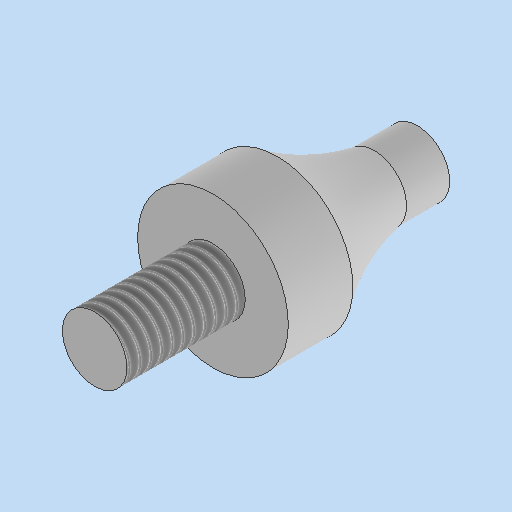
# Autodesk Inventor part: MM0948AN125_G02_100
Saved by Autodesk Inventor 2023.3 (Build 273359000, 359)
## iProperties
Created: 2024-01-18
Part Number: MM0948AN125_G02_100
Material: xStahl_AnP_Dummymaterial
Description: =<RBPARTNOTITLE2>
Vendor: Albert Kuhn
Document SubType Name: Modeling
Designer: RIC7AN
Mass: 1.94193 g
Surface Area: 2.54828 cm^2
Volume: 0.247379 cm^3
Density: 7.85 g/cm^3
Appearance: Vorgabe(1)
RBPARTMADEOF: Hydraulik Schmiernippel H1 M 3 x 0,5, SW7, DIN 71412, Form A, Stahl verzinkt
RBDRAWINGMISSINGSPEC: --
AnP_Kategorie: 2
RBPARTNOTITLE2: Schmiernippel
RBGBREMARKSINDEX: E
RBSURFACE: --
RBPARTNOTITLE1: lubrication nipple
AnP_Material: =<Material>
RBMATERIAL: --
RBMATNO: =<Part Number>
RBPARTNO: SIEHE MNR
Author: RIC7AN
Keywords: =<RBPARTMADEOF>
Comments: =<RBSURFACE2>
Revision Number: 01
Autodesk Inventor part; units mm, degrees
ref_plane "YZ Plane" through (0, 0, 0) normal (1, 0, 0) x (0, 1, 0)
ref_plane "XZ Plane" through (0, 0, 0) normal (0, 1, 0) x (-1, 0, 0)
ref_plane "XY Plane" through (0, 0, 0) normal (0, 0, 1) x (1, 0, 0)
sketch "Skizze1" plane through (0, 0, 0) normal (0, 0, 1) x (1, 0, 0)
  line L0 (0, 0) -> (3.5, 0)
  line L1 (3.5, 0) -> (3.5, 3)
  line L2 (3.5, 3) -> (0, 3)
  line L3 (0, 3) -> (0, 0)
  line L4 (1.3123, 9.5) -> (0, 9.5)
  line L5 (0, 0) -> (1.5, 0)
  line L6 (1.5, 0) -> (1.5, -5.5)
  line L7 (1.5, -5.5) -> (0, -5.5)
  line L8 (0, -5.5) -> (0, 0)
  arc A0 (1.3123, 9.5) -> (3.5, 3) centre (12.0625, 9.5) ccw
  line L9 (0, 9.5) -> (1.5, 9.5)
  line L10 (1.5, 9.5) -> (1.5, 7.5)
  line L11 (1.5, 7.5) -> (0, 7.5)
  line L12 (0, 7.5) -> (0, 9.5)
  line L13 (0, 7.5) -> (0, 3)
  point P0 (0.8535, 7.5)
  dimension "d0" = 1.5
  dimension "d1" = 5.5
  dimension "d2" = 15
  dimension "d3" = 3.5
  dimension "d4" = 1.5
  dimension "d5" = 2
  dimension "d6" = 3
  constraints: 28 end point, 6 parallel, 4 horizontal, 3 perpendicular, 3 point on circle, 1 centre point, 1 collinear, 1 line through centre, 1 vertical
  measures "d0" distance of L6.end L7.end
  measures "d1" distance of L5.end L6.end
  measures "d2" distance between parallel lines of L7 L4
  measures "d3" distance of L1.end L2.end
  measures "d4" distance of L4.end L9.end
  measures "d5" distance of L9.end L10.end
  measures "d6" distance of L0.end L1.end
revolve "Umdrehung1" add sketch "Skizze1" angle 360 about axis through (0, 3, 0) along (0, -1, 0)
thread "Gewinde1" size "M3x0.5" designation "M3" class "6g" standard "ISO Metric profile" length 15.9
